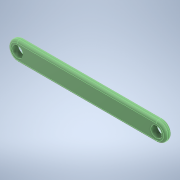
# Autodesk Inventor part: connecting_link
Saved by Autodesk Inventor 2022 (Build 260153000, 153)
## iProperties
Created: 2024-11-08
Part Number: connecting_link
Material: Generic
Document SubType Name: Modeling
Designer: Dell
Density: 1 g/cm^3
Appearance: Smooth - Dark Forest Green
Author: Dell
Autodesk Inventor part; units mm, degrees
ref_plane "YZ Plane" through (0, 0, 0) normal (1, 0, 0) x (0, 1, 0)
ref_plane "XZ Plane" through (0, 0, 0) normal (0, 1, 0) x (-1, 0, 0)
ref_plane "XY Plane" through (0, 0, 0) normal (0, 0, 1) x (1, 0, 0)
sketch "Sketch1" plane through (0, 0, 0) normal (0, 0, 1) x (1, 0, 0)
  line L0 (0, 3) -> (-44, 3) construction
  line L1 (0, 0) -> (-44, 0)
  line L2 (-44, 6) -> (0, 6)
  arc A0 (0, 0) -> (0, 6) centre (0, 3) ccw
  arc A1 (-44, 6) -> (-44, 0) centre (-44, 3) ccw
  circle A2 centre (0, 3) radius 1.75
  circle A3 centre (-44, 3) radius 1.75
  point P0 (0, 0)
  point P1 (-22, 3)
  dimension "d2" = 3
  dimension "d3" = 50
  dimension "d4" = 3.5
  dimension "d5" = 3.5
  dimension "d6" = 0
  dimension "d7" = 0
  constraints: 8 end point, 4 centre point, 4 point on circle, 4 tangent, 2 coincident, 1 horizontal, 1 midpoint, 1 parallel
  measures "d2" radius of A0
  measures "d4" diameter of A2
  measures "d5" diameter of A3
  measures "d6" horizontal distance of point (0, 0) L0.start
  measures "d7" distance from line of point (0, 0) L1
extrude "Extrusion1" add sketch "Sketch1" along normal blind 2
fillet "Fillet1" radius 0.7 8 edges at (-47, 3, 2) (-22, 0, 2) (3, 3, 2) (-22, 6, 2) (-47, 3, 0) (-22, 0, 0) (3, 3, 0) (-22, 6, 0)
body "Solid1"
